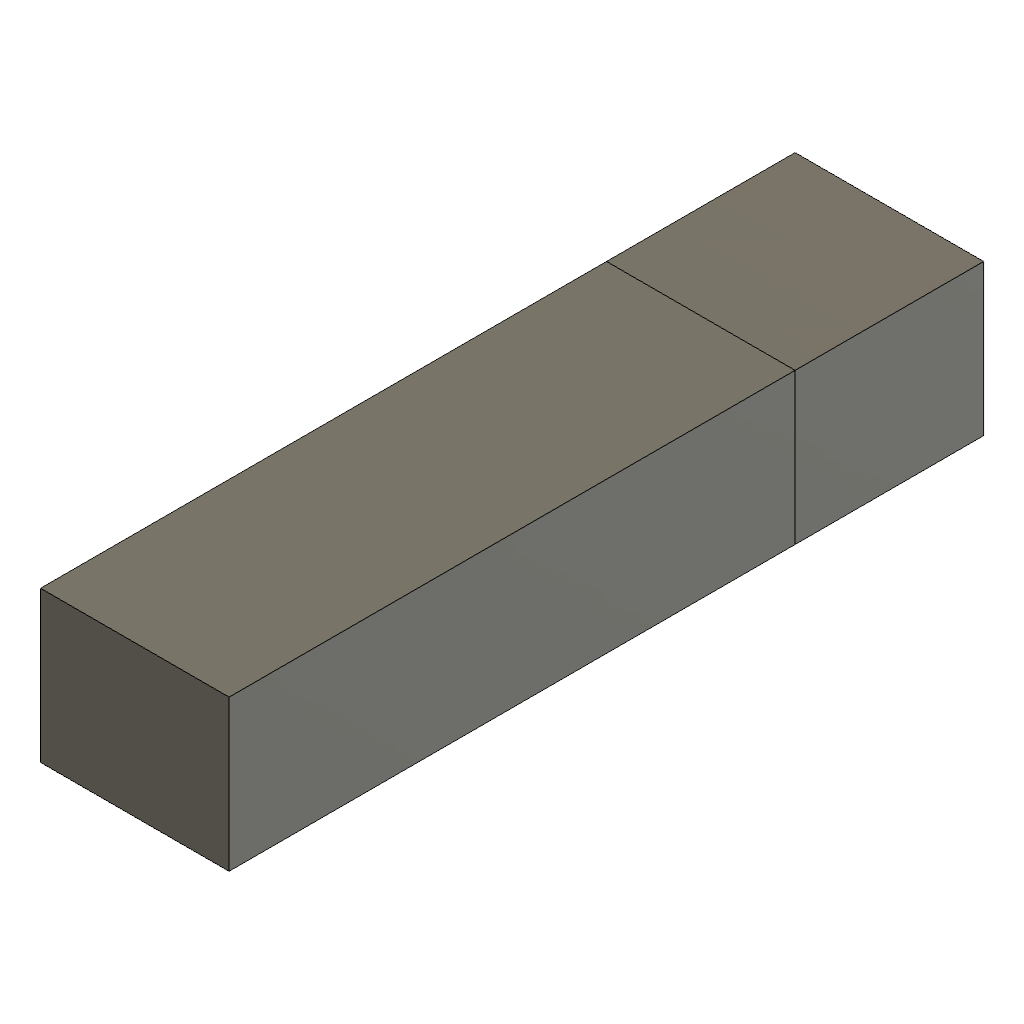
planar_face (Autodesk Fusion 360 design; units mm, degrees)
part number: 2026-10-20-22-24-57-802
Autodesk Fusion 360 part; units mm, degrees
sketch "SweepProfileSection" plane through (0, 0, 0) normal (0, 0, 1) x (1, 0, 0)
  line L0 (-5, -4) -> (5, -4)
  line L1 (5, -4) -> (5, 4)
  line L2 (5, 4) -> (-5, 4)
  line L3 (-5, 4) -> (-5, -4)
extrude "SweepProfileSeed" add sketch "SweepProfileSection" along normal blind 10 makes body 1
sketch "SweepProfilePath" plane through (0, 0, 0) normal (0, 1, 0) x (1, 0, 0)
  line L0 (0, -10) -> (0, -40)
sweep "ProbeSweepProfile" add 1 faces at (-1.6667, 1.3333, 10) path "SweepProfilePath" along L0 separate body on bodies 1 makes body 2
named bodies: "SweepProfileSeedBody"
